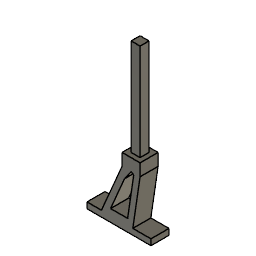
Rear Frame Mount (Autodesk Fusion 360 design; units mm, degrees)
Autodesk Fusion 360 part; units mm, degrees
sketch "Sketch1" plane through (0, 0, 0) normal (0, 1, 0) x (1, 0, 0)
  line L0 (0, 0) -> (-25.4, 0)
  line L1 (-25.4, 0) -> (-25.4, -3.175)
  line L2 (-25.4, -3.175) -> (0, -3.175)
  line L3 (0, -3.175) -> (0, 0)
  line L4 (-25.4, 0) -> (-33.655, 0)
  line L5 (-33.655, 0) -> (-33.655, -3.175)
  line L6 (-33.655, -3.175) -> (-25.4, -3.175)
  line L7 (-25.4, -3.175) -> (-25.4, 0)
  line L8 (-26.035, -3.175) -> (-15.24, -28.575)
  line L9 (-15.24, -28.575) -> (-5.715, -28.575)
  line L10 (-5.715, -28.575) -> (-9.525, -3.175)
  line L11 (-15.24, -28.575) -> (-5.715, -28.575)
  line L12 (-5.715, -28.575) -> (-5.715, -34.925)
  line L13 (-5.715, -34.925) -> (-15.24, -34.925)
  line L14 (-15.24, -34.925) -> (-15.24, -28.575)
  dimension "d3" = 33.655
  dimension "d4" = 8.255
  dimension "d5" = 25.4
  dimension "d6" = 3.175
  dimension "d7" = 3.175
  dimension "d26" = 6.35
  dimension "d27" = 25.4
  dimension "d28" = 9.525
  dimension "d30" = 16.51
  dimension "d31" = 3.81
  dimension "d32" = 9.525
  constraint horizontal L0
  constraint vertical L1
  constraint horizontal L2
  constraint vertical L3
  constraint coincident L0.start L3.end
  constraint horizontal L4
  constraint vertical L5
  constraint horizontal L6
  constraint vertical L7
  constraint coincident L2 L8.start
  constraint perpendicular L1 L9
  constraint coincident L2 L10.end
  constraint horizontal L11
  constraint vertical L12
  constraint horizontal L13
  constraint vertical L14
  constraint horizontal L0.end L4.end
  measures "d3" distance of L3 L5
  measures "d4" distance of L0.end L4.end
  measures "d5" distance of L0.start L0.end
  measures "d6" distance of L4.end L5.end
  measures "d7" distance of L0.start L2.end
  measures "d26" distance of L9.end L12.end
  measures "d27" distance of L2 L9
  measures "d28" distance of L12 L14
  measures "d30" distance of L8.start L10.end
  measures "d31" horizontal distance of L10.end L9.end
  measures "d32" distance of L2.end L10.end
extrude "Extrude1" add sketch "Sketch1" along normal blind 9.525
sketch "Sketch2" plane through (0, 0, 3.175) normal (0, 0, 1) x (-1, 0, 0)
  line L0 (33.655, 0) -> (26.035, 0)
  line L1 (0, 0) -> (0, -9.525)
  line L2 (26.035, -9.525) -> (33.655, -9.525)
  line L3 (33.655, -9.525) -> (33.655, 0)
  circle A0 centre (28.8925, -4.7625) radius 2.1971
  circle A1 centre (3.4925, -4.7625) radius 2.1971
  line L4 (26.035, 0) -> (26.035, -9.525)
  line L5 (9.525, 0) -> (0, 0)
  line L6 (0, -9.525) -> (9.525, -9.525)
  line L7 (9.525, -9.525) -> (9.525, 0)
  dimension "d10" = 4.3942
  dimension "d11" = 4.3942
  dimension "d12" = 4.7625
  dimension "d13" = 4.7625
  dimension "d14" = 25.4
  dimension "d15" = 4.7625
  measures "d10" diameter of A0
  measures "d11" diameter of A1
  measures "d12" distance of L2 A0.centre
  measures "d13" distance of L2 A1.centre
  measures "d14" distance of A0.centre A1.centre
  measures "d15" distance of L3 A0.centre
sketch "Sketch5" plane through (0, 0, 34.925) normal (0, 0, 1) x (-1, 0, 0)
  line L0 (15.24, 0) -> (5.715, 0)
  line L1 (5.715, 0) -> (5.715, -9.525)
  line L2 (5.715, -9.525) -> (15.24, -9.525)
  line L3 (15.24, -9.525) -> (15.24, 0)
  line L4 (12.8588, -7.1437) -> (8.0962, -7.1438)
  line L5 (8.0962, -7.1438) -> (8.0962, -2.3812)
  line L6 (8.0962, -2.3812) -> (12.8588, -2.3813)
  line L7 (12.8588, -2.3813) -> (12.8588, -7.1437)
  dimension "d33" = 4.7625
  dimension "d34" = 4.7625
  dimension "d35" = 2.3813
  dimension "d36" = 2.3813
  constraint horizontal L4
  constraint vertical L5
  constraint horizontal L6
  constraint vertical L7
  measures "d33" distance of L4.end L5.end
  measures "d34" distance of L4.start L4.end
  measures "d35" distance of L2 L4
  measures "d36" distance of L1 L5
extrude "Extrude5" add sketch "Sketch5" along normal blind 50.8 contours L4 L5 L6 L7
sketch "Sketch6" plane through (0, 0, 0) normal (0, -1, 0) x (1, 0, 0)
  line L0 (-9.525, 3.175) -> (-5.715, 28.575)
  line L1 (-5.715, 28.575) -> (-5.715, 34.925)
  line L2 (-5.715, 34.925) -> (-15.24, 34.925)
  line L3 (-15.24, 34.925) -> (-15.24, 28.575)
  line L4 (-15.24, 28.575) -> (-26.035, 3.175)
  line L5 (-26.035, 3.175) -> (-33.655, 3.175)
  line L6 (-33.655, 3.175) -> (-33.655, 0)
  line L7 (-33.655, 0) -> (0, 0)
  line L8 (0, 0) -> (0, 3.175)
  line L9 (0, 3.175) -> (-9.525, 3.175)
  line L10 (-21.2358, 6.35) -> (-12.2593, 6.35)
  line L11 (-12.2593, 6.35) -> (-8.9255, 28.575)
  line L12 (-8.9255, 28.575) -> (-11.7902, 28.575)
  line L13 (-11.7902, 28.575) -> (-21.2358, 6.35)
  line L14 (-13.9069, 23.5944) -> (-10.3578, 28.575)
  line L15 (-10.3578, 28.575) -> (-9.0638, 27.6529)
  dimension "d39" = 6.35
  dimension "d40" = 6.35
  dimension "d41" = 3.175
  dimension "d42" = 3.175
  dimension "d43" = 90
  dimension "d44" = 6.1157
  constraint horizontal L10
  constraint parallel L10 L12
  constraint parallel L4 L13
  constraint coincident L10.start L13.end
  constraint parallel L0 L11
  constraint coincident L13 L14.start
  constraint midpoint L12 L14.end
  constraint coincident L11 L15.end
  measures "d39" distance of L7 L10
  measures "d40" distance of L2 L12
  measures "d41" distance of L0 L11
  measures "d42" distance of L4 L13
  measures "d43" angle of L14 L15
  measures "d44" distance of L14.start L14.end
extrude "Extrude6" cut sketch "Sketch6" against normal blind 9.525 contours L10 L11 L13 L14 L15
equation "d3 = 1.375 in - 0.05 in"
equation "d4 = 0.375 in - 0.05 in"
equation "d12 = ( 0.375 / 2 ) * 1 in"
equation "d13 = ( 3 / 16 ) * 1 in"
equation "d15 = ( 3 / 16 ) * 1 in"
equation "d28 = ( 3 / 8 ) * 1 in"
equation "d33 = ( 3 / 16 ) * 1 in"
equation "d34 = ( 3 / 16 ) * 1 in"
equation "d35 = ( 3 / 32 ) * 1 in"
equation "d36 = ( 3 / 32 ) * 1 in"
